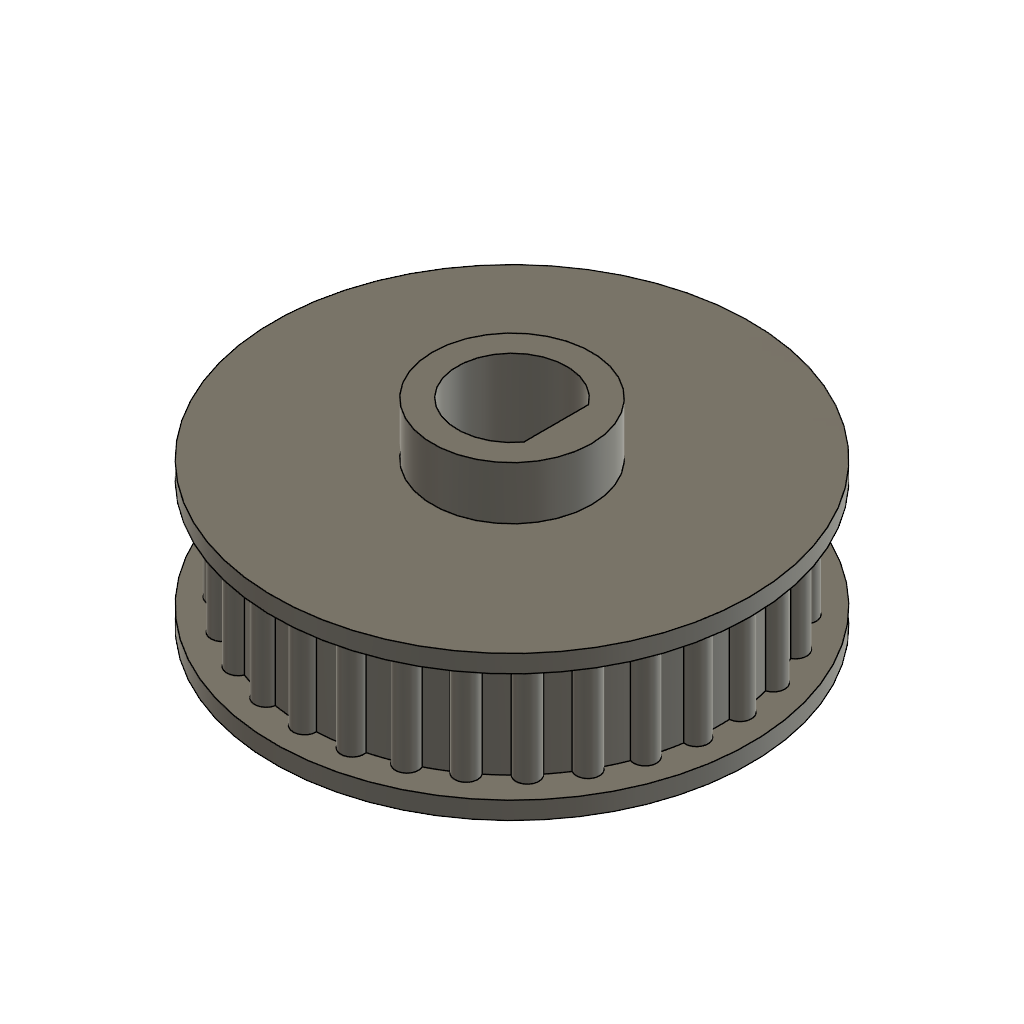
02-22_모터풀리_30T (Autodesk Fusion 360 design; units mm, degrees)
Autodesk Fusion 360 part; units mm, degrees
sketch "스케치1" plane through (0, 0, 0) normal (0, 1, 0) x (1, 0, 0)
  circle A0 centre (0, 0) radius 13.5
  dimension "d1" = 27
  constraint coincident A0.centre origin
  measures "d1" diameter of A0
extrude "돌출1" add sketch "스케치1" along normal blind 1
sketch "스케치2" plane through (0, 1, 0) normal (0, 1, 0) x (-1, 0, 0)
  circle A0 centre (0, 0) radius 13.5
  arc A1 (6.3702, -9.8733) -> (7.4216, -9.1095) centre (6.9065, -9.5059) ccw
  arc A2 (4.1783, -10.982) -> (5.3654, -10.4535) centre (4.7792, -10.7342) ccw
  arc A3 (1.8037, -11.6107) -> (3.0748, -11.3406) centre (2.443, -11.4932) ccw
  arc A4 (-0.6498, -11.732) -> (0.6498, -11.732) centre (0, -11.75) ccw
  arc A5 (-3.0748, -11.3406) -> (-1.8037, -11.6107) centre (-2.443, -11.4932) ccw
  arc A6 (-5.3654, -10.4535) -> (-4.1783, -10.982) centre (-4.7792, -10.7342) ccw
  arc A7 (-7.4216, -9.1095) -> (-6.3702, -9.8733) centre (-6.9065, -9.5059) ccw
  arc A8 (-9.1534, -7.3674) -> (-8.2838, -8.3331) centre (-8.732, -7.8623) ccw
  arc A9 (-10.4851, -5.3033) -> (-9.8354, -6.4287) centre (-10.1758, -5.875) ccw
  arc A10 (-11.3586, -3.0074) -> (-10.957, -4.2433) centre (-11.1749, -3.6309) ccw
  arc A11 (-11.7357, -0.5801) -> (-11.5998, -1.8725) centre (-11.6856, -1.2282) ccw
  arc A12 (-11.5998, 1.8725) -> (-11.7357, 0.5801) centre (-11.6856, 1.2282) ccw
  arc A13 (-10.957, 4.2433) -> (-11.3586, 3.0074) centre (-11.1749, 3.6309) ccw
  arc A14 (-9.8354, 6.4287) -> (-10.4851, 5.3033) centre (-10.1758, 5.875) ccw
  arc A15 (-8.2838, 8.3331) -> (-9.1534, 7.3674) centre (-8.732, 7.8623) ccw
  arc A16 (-6.3702, 9.8733) -> (-7.4216, 9.1095) centre (-6.9065, 9.5059) ccw
  arc A17 (-4.1783, 10.982) -> (-5.3654, 10.4535) centre (-4.7792, 10.7342) ccw
  arc A18 (-1.8037, 11.6107) -> (-3.0748, 11.3406) centre (-2.443, 11.4932) ccw
  arc A19 (0.6498, 11.732) -> (-0.6498, 11.732) centre (0, 11.75) ccw
  arc A20 (3.0748, 11.3406) -> (1.8037, 11.6107) centre (2.443, 11.4932) ccw
  arc A21 (5.3654, 10.4535) -> (4.1783, 10.982) centre (4.7792, 10.7342) ccw
  arc A22 (7.4216, 9.1095) -> (6.3702, 9.8733) centre (6.9065, 9.5059) ccw
  arc A23 (9.1534, 7.3674) -> (8.2838, 8.3331) centre (8.732, 7.8623) ccw
  arc A24 (10.4851, 5.3033) -> (9.8354, 6.4287) centre (10.1758, 5.875) ccw
  arc A25 (11.3586, 3.0074) -> (10.957, 4.2433) centre (11.1749, 3.6309) ccw
  arc A26 (11.7357, 0.5801) -> (11.5998, 1.8725) centre (11.6856, 1.2282) ccw
  arc A27 (11.5998, -1.8725) -> (11.7357, -0.5801) centre (11.6856, -1.2282) ccw
  arc A28 (10.957, -4.2433) -> (11.3586, -3.0074) centre (11.1749, -3.6309) ccw
  arc A29 (9.8354, -6.4287) -> (10.4851, -5.3033) centre (10.1758, -5.875) ccw
  arc A30 (8.2838, -8.3331) -> (9.1534, -7.3674) centre (8.732, -7.8623) ccw
  arc A31 (5.3654, -10.4535) -> (6.3702, -9.8733) centre (0, 0) ccw
  arc A32 (3.0748, -11.3406) -> (4.1783, -10.982) centre (0, 0) ccw
  arc A33 (0.6498, -11.732) -> (1.8037, -11.6107) centre (0, 0) ccw
  arc A34 (-1.8037, -11.6107) -> (-0.6498, -11.732) centre (0, 0) ccw
  arc A35 (-4.1783, -10.982) -> (-3.0748, -11.3406) centre (0, 0) ccw
  arc A36 (-6.3702, -9.8733) -> (-5.3654, -10.4535) centre (0, 0) ccw
  arc A37 (-8.2838, -8.3331) -> (-7.4216, -9.1095) centre (0, 0) ccw
  arc A38 (-9.8354, -6.4287) -> (-9.1534, -7.3674) centre (0, 0) ccw
  arc A39 (-10.957, -4.2433) -> (-10.4851, -5.3033) centre (0, 0) ccw
  arc A40 (-11.5998, -1.8725) -> (-11.3586, -3.0074) centre (0, 0) ccw
  arc A41 (-11.7357, 0.5801) -> (-11.7357, -0.5801) centre (0, 0) ccw
  arc A42 (-11.3586, 3.0074) -> (-11.5998, 1.8725) centre (0, 0) ccw
  arc A43 (-10.4851, 5.3033) -> (-10.957, 4.2433) centre (0, 0) ccw
  arc A44 (-9.1534, 7.3674) -> (-9.8354, 6.4287) centre (0, 0) ccw
  arc A45 (-7.4216, 9.1095) -> (-8.2838, 8.3331) centre (0, 0) ccw
  arc A46 (-5.3654, 10.4535) -> (-6.3702, 9.8733) centre (0, 0) ccw
  arc A47 (-3.0748, 11.3406) -> (-4.1783, 10.982) centre (0, 0) ccw
  arc A48 (-0.6498, 11.732) -> (-1.8037, 11.6107) centre (0, 0) ccw
  arc A49 (1.8037, 11.6107) -> (0.6498, 11.732) centre (0, 0) ccw
  arc A50 (4.1783, 10.982) -> (3.0748, 11.3406) centre (0, 0) ccw
  arc A51 (6.3702, 9.8733) -> (5.3654, 10.4535) centre (0, 0) ccw
  arc A52 (8.2838, 8.3331) -> (7.4216, 9.1095) centre (0, 0) ccw
  arc A53 (9.8354, 6.4287) -> (9.1534, 7.3674) centre (0, 0) ccw
  arc A54 (10.957, 4.2433) -> (10.4851, 5.3033) centre (0, 0) ccw
  arc A55 (11.5998, 1.8725) -> (11.3586, 3.0074) centre (0, 0) ccw
  arc A56 (11.7357, -0.5801) -> (11.7357, 0.5801) centre (0, 0) ccw
  arc A57 (11.3586, -3.0074) -> (11.5998, -1.8725) centre (0, 0) ccw
  arc A58 (10.4851, -5.3033) -> (10.957, -4.2433) centre (0, 0) ccw
  arc A59 (7.4216, -9.1095) -> (8.2838, -8.3331) centre (0, 0) ccw
  arc A60 (9.1534, -7.3674) -> (9.8354, -6.4287) centre (0, 0) ccw
  dimension "d20" = 23.5
  dimension "d21" = 1.3
  dimension "d23" = 360
  constraint coincident A0.centre A31.centre
  constraint coincident A4.centre A34
  constraint concentric A31 A32
  constraint concentric A32 A33
  constraint concentric A33 A34
  constraint concentric A34 A35
  constraint concentric A35 A36
  constraint concentric A36 A37
  constraint concentric A37 A38
  constraint concentric A38 A39
  constraint concentric A39 A40
  constraint concentric A40 A41
  constraint concentric A41 A42
  constraint concentric A42 A43
  constraint concentric A43 A44
  constraint concentric A44 A45
  constraint concentric A45 A46
  constraint concentric A46 A47
  constraint concentric A47 A48
  constraint concentric A48 A49
  constraint concentric A49 A50
  constraint concentric A50 A51
  constraint concentric A51 A52
  constraint concentric A52 A53
  constraint concentric A53 A54
  constraint concentric A54 A55
  constraint concentric A55 A56
  constraint concentric A56 A57
  constraint concentric A57 A58
  constraint concentric A58 A60
  constraint concentric A59 A60
  measures "d20" diameter of A59
  measures "d21" diameter of A4
extrude "돌출2" add sketch "스케치2" along normal blind 6.2 contours A1 A2 A3 A4 A5 A6 A7 A8 A9 A10 A11 A12 A13 A14 A15 A16 A17 A18 A19 A20 A21 A22 A23 A24 A25 A26 A27 A28 A29 A30 A31 A32 A33 A34 A35 A36 A37 A38 A39 A40 A41 A42 A43 A44 A45 A46 A47 A48 A49 A50 A51 A52 A53 A54 A55 A56 A57 A58 A59 A60
sketch "스케치3" plane through (0, 7.2, 0) normal (0, 1, 0) x (-1, 0, 0)
  circle A0 centre (0, 0) radius 13.5
  arc A1 (9.1534, -7.3674) -> (9.8354, -6.4287) centre (0, 0) ccw
  arc A2 (9.8354, -6.4287) -> (10.4851, -5.3033) centre (10.1758, -5.875) ccw
  arc A3 (10.4851, -5.3033) -> (10.957, -4.2433) centre (0, 0) ccw
  arc A4 (10.957, -4.2433) -> (11.3586, -3.0074) centre (11.1749, -3.6309) ccw
  arc A5 (11.3586, -3.0074) -> (11.5998, -1.8725) centre (0, 0) ccw
  arc A6 (11.5998, -1.8725) -> (11.7357, -0.5801) centre (11.6856, -1.2282) ccw
  arc A7 (11.7357, -0.5801) -> (11.7357, 0.5801) centre (0, 0) ccw
  arc A8 (11.7357, 0.5801) -> (11.5998, 1.8725) centre (11.6856, 1.2282) ccw
  arc A9 (11.5998, 1.8725) -> (11.3586, 3.0074) centre (0, 0) ccw
  arc A10 (11.3586, 3.0074) -> (10.957, 4.2433) centre (11.1749, 3.6309) ccw
  arc A11 (10.957, 4.2433) -> (10.4851, 5.3033) centre (0, 0) ccw
  arc A12 (10.4851, 5.3033) -> (9.8354, 6.4287) centre (10.1758, 5.875) ccw
  arc A13 (9.8354, 6.4287) -> (9.1534, 7.3674) centre (0, 0) ccw
  arc A14 (9.1534, 7.3674) -> (8.2838, 8.3331) centre (8.732, 7.8623) ccw
  arc A15 (8.2838, 8.3331) -> (7.4216, 9.1095) centre (0, 0) ccw
  arc A16 (7.4216, 9.1095) -> (6.3702, 9.8733) centre (6.9065, 9.5059) ccw
  arc A17 (6.3702, 9.8733) -> (5.3654, 10.4535) centre (0, 0) ccw
  arc A18 (5.3654, 10.4535) -> (4.1783, 10.982) centre (4.7792, 10.7342) ccw
  arc A19 (4.1783, 10.982) -> (3.0748, 11.3406) centre (0, 0) ccw
  arc A20 (3.0748, 11.3406) -> (1.8037, 11.6107) centre (2.443, 11.4932) ccw
  arc A21 (1.8037, 11.6107) -> (0.6498, 11.732) centre (0, 0) ccw
  arc A22 (0.6498, 11.732) -> (-0.6498, 11.732) centre (0, 11.75) ccw
  arc A23 (-0.6498, 11.732) -> (-1.8037, 11.6107) centre (0, 0) ccw
  arc A24 (-1.8037, 11.6107) -> (-3.0748, 11.3406) centre (-2.443, 11.4932) ccw
  arc A25 (-3.0748, 11.3406) -> (-4.1783, 10.982) centre (0, 0) ccw
  arc A26 (-4.1783, 10.982) -> (-5.3654, 10.4535) centre (-4.7792, 10.7342) ccw
  arc A27 (-5.3654, 10.4535) -> (-6.3702, 9.8733) centre (0, 0) ccw
  arc A28 (-6.3702, 9.8733) -> (-7.4216, 9.1095) centre (-6.9065, 9.5059) ccw
  arc A29 (-7.4216, 9.1095) -> (-8.2838, 8.3331) centre (0, 0) ccw
  arc A30 (-8.2838, 8.3331) -> (-9.1534, 7.3674) centre (-8.732, 7.8623) ccw
  arc A31 (-9.1534, 7.3674) -> (-9.8354, 6.4287) centre (0, 0) ccw
  arc A32 (-9.8354, 6.4287) -> (-10.4851, 5.3033) centre (-10.1758, 5.875) ccw
  arc A33 (-10.4851, 5.3033) -> (-10.957, 4.2433) centre (0, 0) ccw
  arc A34 (-10.957, 4.2433) -> (-11.3586, 3.0074) centre (-11.1749, 3.6309) ccw
  arc A35 (-11.3586, 3.0074) -> (-11.5998, 1.8725) centre (0, 0) ccw
  arc A36 (-11.5998, 1.8725) -> (-11.7357, 0.5801) centre (-11.6856, 1.2282) ccw
  arc A37 (-11.7357, 0.5801) -> (-11.7357, -0.5801) centre (0, 0) ccw
  arc A38 (-11.7357, -0.5801) -> (-11.5998, -1.8725) centre (-11.6856, -1.2282) ccw
  arc A39 (-11.5998, -1.8725) -> (-11.3586, -3.0074) centre (0, 0) ccw
  arc A40 (-11.3586, -3.0074) -> (-10.957, -4.2433) centre (-11.1749, -3.6309) ccw
  arc A41 (-10.957, -4.2433) -> (-10.4851, -5.3033) centre (0, 0) ccw
  arc A42 (-10.4851, -5.3033) -> (-9.8354, -6.4287) centre (-10.1758, -5.875) ccw
  arc A43 (-9.8354, -6.4287) -> (-9.1534, -7.3674) centre (0, 0) ccw
  arc A44 (-9.1534, -7.3674) -> (-8.2838, -8.3331) centre (-8.732, -7.8623) ccw
  arc A45 (-8.2838, -8.3331) -> (-7.4216, -9.1095) centre (0, 0) ccw
  arc A46 (-7.4216, -9.1095) -> (-6.3702, -9.8733) centre (-6.9065, -9.5059) ccw
  arc A47 (-6.3702, -9.8733) -> (-5.3654, -10.4535) centre (0, 0) ccw
  arc A48 (-5.3654, -10.4535) -> (-4.1783, -10.982) centre (-4.7792, -10.7342) ccw
  arc A49 (-4.1783, -10.982) -> (-3.0748, -11.3406) centre (0, 0) ccw
  arc A50 (-3.0748, -11.3406) -> (-1.8037, -11.6107) centre (-2.443, -11.4932) ccw
  arc A51 (-1.8037, -11.6107) -> (-0.6498, -11.732) centre (0, 0) ccw
  arc A52 (-0.6498, -11.732) -> (0.6498, -11.732) centre (0, -11.75) ccw
  arc A53 (0.6498, -11.732) -> (1.8037, -11.6107) centre (0, 0) ccw
  arc A54 (1.8037, -11.6107) -> (3.0748, -11.3406) centre (2.443, -11.4932) ccw
  arc A55 (3.0748, -11.3406) -> (4.1783, -10.982) centre (0, 0) ccw
  arc A56 (4.1783, -10.982) -> (5.3654, -10.4535) centre (4.7792, -10.7342) ccw
  arc A57 (5.3654, -10.4535) -> (6.3702, -9.8733) centre (0, 0) ccw
  arc A58 (6.3702, -9.8733) -> (7.4216, -9.1095) centre (6.9065, -9.5059) ccw
  arc A59 (7.4216, -9.1095) -> (8.2838, -8.3331) centre (0, 0) ccw
  arc A60 (8.2838, -8.3331) -> (9.1534, -7.3674) centre (8.732, -7.8623) ccw
  dimension "d10" = 27
  constraint coincident A0.centre A1.centre
  measures "d10" diameter of A0
extrude "돌출3" add sketch "스케치3" along normal blind 1 contours A0 | A1 A2 A3 A4 A5 A6 A7 A8 A9 A10 A11 A12 A13 A14 A15 A16 A17 A18 A19 A20 A21 A22 A23 A24 A25 A26 A27 A28 A29 A30 A31 A32 A33 A34 A35 A36 A37 A38 A39 A40 A41 A42 A43 A44 A45 A46 A47 A48 A49 A50 A51 A52 A53 A54 A55 A56 A57 A58 A59 A60
sketch "스케치4" plane through (0, 8.2, 0) normal (0, 1, 0) x (-1, 0, 0)
  circle A0 centre (0, 0) radius 13.5
  circle A1 centre (0, 0) radius 4.5
  circle A2 centre (0, 0) radius 3.1
  line L0 (-2.5, -1.833) -> (-2.5, 1.833)
  dimension "d13" = 9
  dimension "d14" = 6.2
  dimension "d15" = 2.5
  constraint coincident A0.centre A1.centre
  constraint coincident A2 L0.start
  constraint coincident A2 L0.end
  constraint vertical L0
  measures "d13" diameter of A1
  measures "d14" diameter of A2
  measures "d15" distance of A0.centre L0
extrude "돌출4" cut sketch "스케치4" against normal blind 5.8 contours A2 L0 picked at (-0.6446, 0.152)
extrude "돌출5" add sketch "스케치4" along normal blind 3 contours A1 | A2 L0 picked at (-2.5774, -0.4882)
extrude "돌출6" cut 1 faces at (0.5894, 2.4, 0.7953) along direction (0, -1, 0) blind 1
